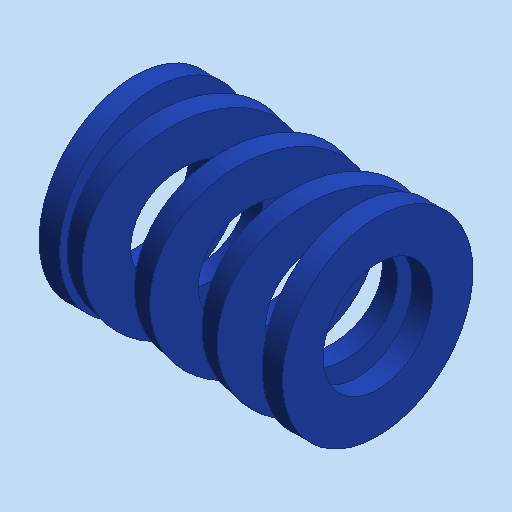
# Autodesk Inventor part: MM0948AN120_G02_100
Saved by Autodesk Inventor 2023.3 (Build 273359000, 359)
## iProperties
Part Number: MM0948AN120_G02_100
Material: Generisch
Catalog Web Link: www.cadenas.de
Description: =<RBPARTNOTITLE2>
Vendor: Steinel
Document SubType Name: Modeling
Designer: partserver
Manufacturer: STEINEL
Mass: 4.43048 g
Surface Area: 49.7309 cm^2
Volume: 4.43048 cm^3
Density: 1 g/cm^3
Appearance: blau AnP
Category: PARTsolutions
Company: STEINEL
PSOL_IDENT_0: {$CADENAS_DATA\23d-libs\steinel\federelemente_5\sz_8010.prj},201 {VTYP=3D},{NB=SZ 8010.25 x 032 (0B)
PSOL_IDENT_1: },{LINA=SZ 8010.25 x 032},{NN=SZ 8010},{DATE=27.08.2020 07:34:24},{GEOMDATE=07.05.2020 08:49:40},{VE
PSOL_IDENT_2: RSION=},{LINEID=440},{WBVAR=DARSTELLUNG,HUBST},{WBNUMERIC=HUBST}  {NB=SZ 8010.25 x 032 (0B)},{LINA=S
PSOL_IDENT_3: Z 8010.25 x 032},{KT=DUMMY},{BESTNR=SZ 8010.25 x 032},{DARSTELLUNG=B},{HUBST=0.0},{DH=25.0},{DD=12.5
PSOL_IDENT_4: },{LO=32},{C=80.3},{S1=9.6},{F1=771},{S2=12.8},{F2=1028},{X=5.3},{Y=2.7},{ML=11.200},{FN=1027.000},{
PSOL_IDENT_5: MF=16.000},{SN=10.000},{N=3},{G=25.000},{DIST=1.900},{WG=0},{FUNC=Damping, Cushioning}
NB: SZ 8010.25 x 032 (0B)
NN: SZ 8010
NT: System spring, light load
NBSYN: $BESTNR. ($HUBST.$DARSTELLUNG.)
LINA: SZ 8010.25 x 032
CATALOG: Steinel Normalien
BESTNR: SZ 8010.25 x 032
DARSTELLUNG: General representation
HUBST: 0
DH: 25
DD: 12.5
LO: 32
C: 80.3
S1: 9.6
F1: 771
S2: 12.8
F2: 1028
X: 5.3
Y: 2.7
SUPPLIER: STEINEL
ARTICLENO: SZ 8010.25 x 032 (0B)
BOMINFO: SZ 8010.25 x 032
CREATOR: CADENAS GmbH
RBDRAWINGMISSINGSPEC: --
RBSURFACE: --
RBPARTNOTITLE1: system spring
AnP_Kategorie: 2
AnP_Material: =<Material>
RBPARTMADEOF: SZ 8020 25 x 032
RBPARTNOTITLE2: Systemfeder
RBMATERIAL: =<Material>
RBSURFACE2: --
RBMATNO: =<Part Number>
Title: SZ 8010.25 x 032
Author: Cadenas PARTsolutions
Comments: =<RBSURFACE2>
Keywords: =<RBPARTMADEOF>
Revision Number: 01
Autodesk Inventor part; units mm, degrees
ref_plane "YZ Plane" through (0, 0, 0) normal (1, 0, 0) x (0, 1, 0)
ref_plane "XZ Plane" through (0, 0, 0) normal (0, 1, 0) x (-1, 0, 0)
ref_plane "XY Plane" through (0, 0, 0) normal (0, 0, 1) x (1, 0, 0)
sketch "Sketch_2" plane through (0, 0, 0) normal (1, 0, 0) x (0, 1, 0)
  circle A0 centre (0, 0) radius 12.5
  circle A1 centre (0, 0) radius 7.2
  constraints: 2 centre point
extrude "Extrusion1" add sketch "Sketch_2" along normal blind 2.7
sketch "Sketch_4" plane through (0, 0, 0) normal (1, 0, 0) x (0, 1, 0)
  circle A0 centre (9.85, 0) radius 0.2
  constraints: 1 centre point
extrude "Extrusion2" add sketch "Sketch_4" along normal blind 32
sketch "Sketch_5" plane through (32, 0, 0) normal (1, 0, 0) x (0, 0, -1)
  circle A0 centre (0, 0) radius 12.5
  circle A1 centre (0, 0) radius 7.2
  constraints: 2 centre point
extrude "Extrusion3" add sketch "Sketch_5" against normal blind 2.7
sketch "Sketch_3" plane through (0, 0, 0) normal (0, 0, 1) x (1, 0, 0)
  line L0 (8.3706, 0.312) -> (5.7437, -0.312)
  line L1 (2.8545, 11.8495) -> (4.0795, 6.693)
  line L2 (4.0795, 6.693) -> (6.7064, 7.3171)
  line L3 (6.7064, 7.3171) -> (5.4814, 12.4736)
  line L4 (5.4814, 12.4736) -> (2.8545, 11.8495)
  constraints: 10 end point
revolve "Revolution1" add sketch "Sketch_3" angle 360 about axis through (8.3706, 0.312, 0) along (0.9729, 0.2311, 0)
pattern_linear "Rectangular Pattern1" count 3 spacing 8.8667 along (1, 0, 0) of "Revolution1"
body "Solid1"
